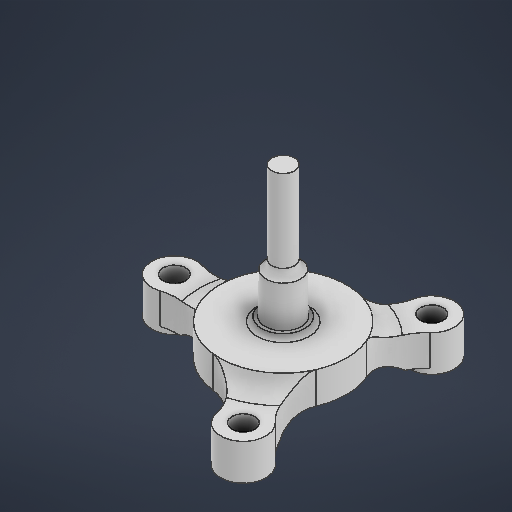
# Autodesk Inventor part: roter
Saved by Autodesk Inventor 2026.2 (Build 302298010, 298A)
## iProperties
Created: 2026-03-26
Part Number: roter
Material: 일반
Document SubType Name: Modeling
Designer: work
Density: 1 g/cm^3
Appearance: 기본값
Author: work
Autodesk Inventor part; units mm, degrees
ref_plane "YZ Plane" through (0, 0, 0) normal (1, 0, 0) x (0, 1, 0)
ref_plane "XZ Plane" through (0, 0, 0) normal (0, 1, 0) x (-1, 0, 0)
ref_plane "XY Plane" through (0, 0, 0) normal (0, 0, 1) x (1, 0, 0)
sketch "스케치1" plane through (0, 0, 0) normal (0, 1, 0) x (-1, 0, 0)
  circle A0 centre (0, 0) radius 24 construction
  circle A1 centre (24, 0) radius 2.5
  line L0 (0, 0) -> (24, 0) construction
  circle A2 centre (0, 0) radius 11
  circle A3 centre (0, 0) radius 14
  circle A4 centre (24, 0) radius 5
  arc A5 (11.2656, 8.3118) -> (22.4375, 4.7496) centre (19.3125, 14.2488) ccw
  arc A6 (22.4375, -4.7496) -> (11.2656, -8.3118) centre (19.3125, -14.2488) ccw
  circle A7 centre (-12, 20.7846) radius 2.5
  line L1 (0, 0) -> (-12, 20.7846) construction
  circle A8 centre (-12, 20.7846) radius 5
  arc A9 (-12.831, 5.6004) -> (-15.332, 17.0567) centre (-21.996, 9.6007) ccw
  arc A10 (-7.1055, 21.8062) -> (1.5654, 13.9122) centre (2.6835, 23.8495) ccw
  circle A11 centre (-12, -20.7846) radius 2.5
  line L2 (0, 0) -> (-12, -20.7846) construction
  circle A12 centre (-12, -20.7846) radius 5
  arc A13 (1.5654, -13.9122) -> (-7.1055, -21.8062) centre (2.6835, -23.8495) ccw
  arc A14 (-15.332, -17.0567) -> (-12.831, -5.6004) centre (-21.996, -9.6007) ccw
  point P0 (-7.1055, 21.8062)
  point P1 (-12.831, -5.6004)
  point P2 (-15.332, -17.0567)
  point P3 (1.5654, -13.9122)
  point P4 (11.2656, -8.3118)
  point P5 (22.4375, -4.7496)
  point P6 (1.5654, 13.9122)
  dimension "d0" = 48
  dimension "d3" = 28
  dimension "d4" = 10
  dimension "d1" = 5
  dimension "d2" = 22
  dimension "d5" = 10
  dimension "d8" = 360
  constraints: 12 point on circle, 10 centre point, 6 coincident, 6 end point, 3 symmetric about line, 1 horizontal, 1 horizontal alignment, 60 other
  measures "d1" diameter of A1
  measures "d2" diameter of A2
  measures "d5" radius of A5
extrude "돌출1" add sketch "스케치1" along normal blind 8
sketch "스케치2" plane through (0, 8, 0) normal (0, 1, 0) x (1, 0, 0)
  circle A0 centre (0, 0) radius 14
  constraints: 1 centre point, 1 coincident
extrude "돌출2" add sketch "스케치2" along normal blind 3
sketch "스케치3" plane through (0, 11, 0) normal (0, 1, 0) x (1, 0, 0)
  circle A0 centre (0, 0) radius 2.5
  dimension "d14" = 5
  constraints: 1 centre point, 1 coincident
  measures "d14" diameter of A0
extrude "돌출3" add sketch "스케치3" along normal blind 30
fillet "모깎기2" radius 5 3 edges at (7, 8, 12.1244) (7, 8, -12.1244) (-14, 8, 0)
sketch "스케치4" plane through (0, 0, 0) normal (0, 0, 1) x (1, 0, 0)
  line L0 (0, 0) -> (0, 5)
  arc A0 (0, 5) -> (-19, 1.2) centre (-5.5, -16.9) ccw
  line L1 (-22.4375, 0) -> (-22.4375, 0) projected
  line L2 (-22.4375, 0) -> (-22.4375, 8) projected
  line L3 (-22.4375, 8) -> (-22.4375, 8) projected
  line L4 (-22.4375, 0) -> (-22.4375, 8) projected
  line L5 (-18.072, 8) -> (-18.072, 8) projected
  line L6 (-18.072, 8) -> (-22.4375, 8) projected
  line L7 (-22.4375, 8) -> (-22.4375, 8) projected
  line L8 (-22.4375, 8) -> (-18.072, 8) projected
  line L9 (-26.5, 8) -> (-21.5, 8) projected
  line L10 (-22.4375, 0) -> (-29, 0) projected
  line L11 (-26.5, 8) -> (-21.5, 8) projected
  line L12 (-26.5, 8) -> (-21.5, 8) projected
  line L13 (-26.5, 0) -> (-21.5, 0) projected
  line L14 (15.332, 0) -> (12.831, 0) projected
  line L15 (7.1055, 0) -> (15.332, 0) projected
  line L16 (-1.5654, 0) -> (7.1055, 0) projected
  line L17 (-11.2656, 0) -> (-1.5654, 0) projected
  line L18 (-22.4375, 0) -> (-11.2656, 0) projected
  line L19 (-22.4375, 0) -> (-22.4375, 0) projected
  line L20 (-11.2656, 0) -> (-22.4375, 0) projected
  line L21 (-1.5654, 0) -> (-11.2656, 0) projected
  line L22 (7.1055, 0) -> (-1.5654, 0) projected
  line L23 (15.332, 0) -> (7.1055, 0) projected
  line L24 (12.831, 0) -> (15.332, 0) projected
  line L25 (12.831, 0) -> (12.831, 0) projected
  line L26 (-26.5, 0) -> (-21.5, 0) projected
  line L27 (-11, 0) -> (11, 0) projected
  line L28 (9.5, 0) -> (14.5, 0) projected
  line L29 (9.5, 0) -> (14.5, 0) projected
  line L30 (-24, 0) -> (-19, 0)
  line L31 (-19, 0) -> (-19, 1.2)
  line L32 (-19, 0) -> (0, 0)
  line L33 (-11, 0) -> (-11, 5)
  dimension "d19" = 5
  dimension "d20" = 5
  dimension "d21" = 1.2
  dimension "d22" = 5
  constraints: 10 end point, 3 point on circle, 2 perpendicular, 1 centre point, 1 collinear, 1 midpoint, 1 point on line, 1 vertical
  measures "d19" distance of L30.start L30.end
  measures "d20" distance of L0.start L0.end
  measures "d21" distance of L30.end L31.end
  measures "d22" distance of L27.start L33.end
revolve "회전1" cut sketch "스케치4" angle 360 about axis through (0, 0, 0) along (0, 1, 0) contours L33 L17 L18 L31 A0
fillet "모깎기3" radius 2 1 edges at (11, 8, 0)
sketch "스케치5" plane through (0, 0, 0) normal (0, -1, 0) x (1, 0, 0)
  arc A0 (-18.5115, 4.2809) -> (-18.5115, -4.2809) centre (0, 0) ccw projected
  arc A1 (-22.4375, 4.7496) -> (-18.5115, 4.2809) centre (-19.3125, 14.2488) ccw projected
  arc A2 (-22.4375, 4.7496) -> (-22.4375, -4.7496) centre (-24, 0) ccw projected
  arc A3 (-18.5115, -4.2809) -> (-22.4375, -4.7496) centre (-19.3125, -14.2488) ccw projected
  circle A4 centre (-24, 0) radius 2.5 projected
  arc A5 (5.5484, -18.1718) -> (12.9631, -13.8909) centre (0, 0) ccw projected
  arc A6 (7.1055, -21.8062) -> (5.5484, -18.1718) centre (-2.6835, -23.8495) ccw projected
  arc A7 (7.1055, -21.8062) -> (15.332, -17.0567) centre (12, -20.7846) ccw projected
  arc A8 (12.9631, -13.8909) -> (15.332, -17.0567) centre (21.996, -9.6007) ccw projected
  circle A9 centre (12, -20.7846) radius 2.5 projected
  circle A10 centre (12, 20.7846) radius 2.5 projected
  arc A11 (12.9631, 13.8909) -> (5.5484, 18.1718) centre (0, 0) ccw projected
  arc A12 (15.332, 17.0567) -> (12.9631, 13.8909) centre (21.996, 9.6007) ccw projected
  arc A13 (15.332, 17.0567) -> (7.1055, 21.8062) centre (12, 20.7846) ccw projected
  arc A14 (5.5484, 18.1718) -> (7.1055, 21.8062) centre (-2.6835, 23.8495) ccw projected
  circle A15 centre (12, 20.7846) radius 5
  circle A16 centre (-24, 0) radius 5
  circle A17 centre (12, -20.7846) radius 5
  point P0 (9.5, 16.4545)
  point P1 (9.5, -16.4545)
  point P2 (15.332, -17.0567)
  point P3 (-22.4375, 4.7496)
  point P4 (-19, 0)
  point P5 (-22.4375, -4.7496)
  constraints: 3 coincident, 2 centre point, 2 tangent, 3 other
extrude "돌출4" cut sketch "스케치5" against normal blind 1.2 contours A0 A16 A1 | A0 A3 A16 | A5 A17 A6 | A5 A8 A17 | A11 A15 A12 | A11 A14 A15
sketch "스케치6" plane through (0, 11, 0) normal (0, 1, 0) x (1, 0, 0)
  circle A0 centre (0, 0) radius 4
  dimension "d27" = 8
  constraints: 1 centre point, 1 coincident
  measures "d27" diameter of A0
extrude "돌출5" add sketch "스케치6" along normal blind 10
chamfer "모따기1" distance 10 angle 1 1 edges at (-4, 21, 0) measured on face at (-4, 20.5, 0)
fillet "모깎기4" radius 2 1 edges at (-2.5, 21, 0)
sketch "스케치7" plane through (0, 11, 0) normal (0, 1, 0) x (1, 0, 0)
  circle A0 centre (0, 0) radius 4.75
  dimension "d34" = 9.5
  constraints: 1 centre point, 1 coincident
  measures "d34" diameter of A0
extrude "돌출6" add sketch "스케치7" along normal blind 1
fillet "모깎기5" radius 1 1 edges at (-4.75, 11, 0)
